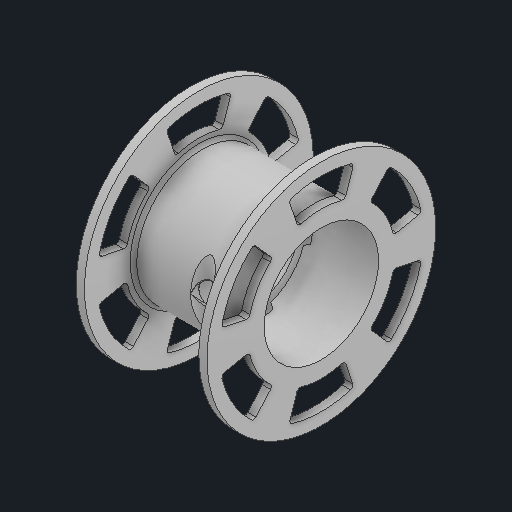
# Autodesk Inventor part: 4_02_Bobine
Saved by Autodesk Inventor 2026 (Build 300175000, 175)
## iProperties
Created: 2025-05-01
Part Number: 4_02_Bobine
Material: Generic
Document SubType Name: Modeling
Designer: AdminForWorker
Density: 1 g/cm^3
Appearance: Default
Title: 4_02_Bobine v3
Author: AdminForWorker
Autodesk Inventor part; units mm, degrees
sketch "Esquisse1" plane through (0, 0, 0) normal (0, 0, 1) x (1, 0, 0)
  line L0 (0.0093, 70) -> (5.0093, 70)
  line L1 (5.0093, 70) -> (5.0093, 40)
  line L2 (0.0093, 70) -> (0.0093, 25.3)
  line L3 (5.0093, 40) -> (75.0093, 40)
  line L4 (75.0093, 40) -> (75.0093, 70)
  line L5 (75.0093, 70) -> (80.0093, 70)
  line L6 (80.0093, 70) -> (80.0093, 35)
  line L7 (80.0093, 35) -> (40.0093, 35)
  line L8 (40.0093, 25.3) -> (40.0093, 35)
  line L9 (-90.7605, 0) -> (228.6248, 0)
  line L10 (40.0093, 25.3) -> (0.0093, 25.3)
  point P0 (0, 0)
  dimension "d2" = 5
  dimension "d3" = 30
  dimension "d4" = 70
  dimension "d5" = 30
  dimension "d6" = 5
  dimension "d7" = 35
  dimension "d8" = 40
  dimension "d9" = 40
  dimension "d10" = 140
  dimension "d12" = 70
  dimension "d20" = 9.7
  constraints: 22 end point, 5 horizontal, 4 perpendicular, 3 vertical
  measures "d2" distance of L0.start L0.end
  measures "d3" distance of L0.end L1.end
  measures "d4" distance of L1.end L3.end
  measures "d5" distance of L3.end L4.end
  measures "d6" distance of L4.end L5.end
  measures "d7" distance of L5.end L6.end
  measures "d8" distance of L6.end L7.end
  measures "d9" distance of L2.end L8.start
  measures "d10" diameter of L0 L9
  measures "d12" diameter of L7 L9
  measures "d20" distance of L8.start L7.end
revolve "Révolution1" add sketch "Esquisse1" angle 360 about axis through (-90.7605, 0, 0) along (1, 0, 0)
sketch "Esquisse2" plane through (0.0093, 0, 0) normal (-1, 0, 0) x (0, 0, 1)
  circle A0 centre (0, 0) radius 30.3 construction
  circle A1 centre (0, 0) radius 35 construction
  line L0 (0, 0) -> (-87.8367, 0) construction
  line L1 (0, 0) -> (94.5103, 0) construction
  line L2 (0, 0) -> (0, 50.6055) construction
  line L3 (0, 0) -> (0, -54.0226) construction
  line L4 (0, 0) -> (-78.2056, 24.1918) construction
  line L5 (0, 0) -> (-24.1308, 78.0083) construction
  line L6 (0, 0) -> (-85.524, -26.4557) construction
  line L7 (0, 0) -> (-24.2483, -78.3883) construction
  line L8 (0, 0) -> (78.2056, 24.1918) construction
  line L9 (0, 0) -> (24.1308, 78.0083) construction
  line L10 (0, 0) -> (85.524, -26.4557) construction
  line L11 (0, 0) -> (24.2483, -78.3883) construction
  line L12 (-28.9467, 8.9543) -> (-33.4368, 10.3432)
  line L13 (-8.9543, 28.9467) -> (-10.3432, 33.4368)
  line L14 (8.9543, 28.9467) -> (10.3432, 33.4368)
  line L15 (28.9467, 8.9543) -> (33.4368, 10.3432)
  line L16 (28.9467, -8.9543) -> (33.4368, -10.3432)
  line L17 (8.9543, -28.9467) -> (10.3432, -33.4368)
  line L18 (-8.9543, -28.9467) -> (-10.3432, -33.4368)
  line L19 (-28.9467, -8.9543) -> (-33.4368, -10.3432)
  arc A2 (33.4368, 10.3432) -> (10.3432, 33.4368) centre (0, 0) ccw
  arc A3 (28.9467, 8.9543) -> (8.9543, 28.9467) centre (0, 0) ccw
  arc A4 (8.9543, -28.9467) -> (28.9467, -8.9543) centre (0, 0) ccw
  arc A5 (10.3432, -33.4368) -> (33.4368, -10.3432) centre (0, 0) ccw
  arc A6 (-28.9467, -8.9543) -> (-8.9543, -28.9467) centre (0, 0) ccw
  arc A7 (-33.4368, -10.3432) -> (-10.3432, -33.4368) centre (0, 0) ccw
  arc A8 (-8.9543, 28.9467) -> (-28.9467, 8.9543) centre (0, 0) ccw
  arc A9 (-10.3432, 33.4368) -> (-33.4368, 10.3432) centre (0, 0) ccw
  dimension "d22" = 60.6
  dimension "d23" = 70
  dimension "d24" = 17.189
  dimension "d25" = 17.189
  dimension "d26" = 17.189
  dimension "d27" = 17.189
  constraints: 40 end point, 16 point on circle, 16 point on line, 9 centre point, 4 concentric, 4 symmetric about line, 2 coincident, 2 horizontal, 2 vertical, 14 other
  measures "d23" diameter of A1
  measures "d24" angle of L4 L0
  measures "d25" angle of L2 L5
  measures "d26" angle of L0 L6
  measures "d27" angle of L3 L7
extrude "Extrusion1" cut sketch "Esquisse2" against normal blind 60
ref_plane "Plan de construction3" through (40.0093, 0, 40) normal (0, 0, 1) x (1, 0, 0)
sketch "Esquisse4" plane through (40.0093, 0, 40) normal (0, 0, 1) x (1, 0, 0)
  line L0 (35, -70) -> (35, 70) projected
  point P0 (-40.0093, 0)
  point P1 (7, 0)
  dimension "d38" = 28
  measures "d38" distance from line of L0 point (7, 0)
hole "Perçage2" at (47.0093, 0, 40) direction (0, 0, -1) diameter 14 end up to surface
sketch "Esquisse5" plane through (0.0093, 0, 0) normal (-1, 0, 0) x (0, 0, 1)
  circle A0 centre (0, 0) radius 40 construction
  circle A1 centre (0, 0) radius 35 projected
  circle A2 centre (0, 0) radius 45 construction
  circle A3 centre (0, 0) radius 62.5 construction
  line L0 (0, 0) -> (93.5731, 0) construction
  line L1 (0, 0) -> (52.3953, -90.7513) construction
  line L2 (0, 0) -> (-52.6354, -91.1672) construction
  line L3 (0, 0) -> (-144.4896, 0) construction
  line L4 (0, 0) -> (-63.0448, 109.1968) construction
  line L5 (0, 0) -> (59.6395, 103.2987) construction
  line L6 (0, 0) -> (-79.7656, 90.2882) construction
  line L7 (0, 0) -> (-41.0094, 122.2745) construction
  line L8 (0, 0) -> (37.125, 110.6925) construction
  line L9 (0, 0) -> (75.0774, 84.9815) construction
  line L10 (0, 0) -> (123.0935, 24.9523) construction
  line L11 (0, 0) -> (-106.2672, 21.5414) construction
  line L12 (0, 0) -> (-63.0448, -109.1968) construction
  line L13 (0, 0) -> (59.6395, -103.2987) construction
  line L14 (0, 0) -> (-79.7656, -90.2882) construction
  line L15 (0, 0) -> (-41.0094, -122.2745) construction
  line L16 (0, 0) -> (37.125, -110.6925) construction
  line L17 (0, 0) -> (75.0774, -84.9815) construction
  line L18 (0, 0) -> (123.0935, -24.9523) construction
  line L19 (0, 0) -> (-106.2672, -21.5414) construction
  line L20 (-14.3091, 42.6644) -> (-19.8738, 59.2561)
  line L21 (14.3091, 42.6644) -> (19.8738, 59.2561)
  line L22 (29.7939, 33.7243) -> (41.3804, 46.8392)
  line L23 (44.103, 8.9401) -> (61.2542, 12.4168)
  line L24 (44.103, -8.9401) -> (61.2542, -12.4168)
  line L25 (29.7939, -33.7243) -> (41.3804, -46.8392)
  line L26 (14.3091, -42.6644) -> (19.8738, -59.2561)
  line L27 (-14.3091, -42.6644) -> (-19.8738, -59.2561)
  line L28 (-29.7939, -33.7243) -> (-41.3804, -46.8392)
  line L29 (-44.103, -8.9401) -> (-61.2542, -12.4168)
  line L30 (-44.103, 8.9401) -> (-61.2542, 12.4168)
  line L31 (-29.7939, 33.7243) -> (-41.3804, 46.8392)
  arc A4 (19.8738, 59.2561) -> (-19.8738, 59.2561) centre (0, 0) ccw
  arc A5 (44.103, 8.9401) -> (29.7939, 33.7243) centre (0, 0) ccw
  arc A6 (14.3091, 42.6644) -> (-14.3091, 42.6644) centre (0, 0) ccw
  arc A7 (61.2542, 12.4168) -> (41.3804, 46.8392) centre (0, 0) ccw
  arc A8 (29.7939, -33.7243) -> (44.103, -8.9401) centre (0, 0) ccw
  arc A9 (41.3804, -46.8392) -> (61.2542, -12.4168) centre (0, 0) ccw
  arc A10 (-14.3091, -42.6644) -> (14.3091, -42.6644) centre (0, 0) ccw
  arc A11 (-19.8738, -59.2561) -> (19.8738, -59.2561) centre (0, 0) ccw
  arc A12 (-44.103, -8.9401) -> (-29.7939, -33.7243) centre (0, 0) ccw
  arc A13 (-61.2542, -12.4168) -> (-41.3804, -46.8392) centre (0, 0) ccw
  arc A14 (-41.3804, 46.8392) -> (-61.2542, 12.4168) centre (0, 0) ccw
  arc A15 (-29.7939, 33.7243) -> (-44.103, 8.9401) centre (0, 0) ccw
  dimension "d47" = 90
  dimension "d48" = 125
  dimension "d46" = 80
  dimension "d50" = 60
  dimension "d51" = 60
  dimension "d52" = 60
  dimension "d53" = 60
  dimension "d54" = 11.459
  dimension "d55" = 11.459
  dimension "d56" = 11.459
  dimension "d57" = 11.459
  dimension "d58" = 11.459
  dimension "d59" = 11.459
  constraints: 64 end point, 24 point on circle, 24 point on line, 13 centre point, 8 symmetric about line, 3 coincident, 2 horizontal, 41 other
  measures "d46" diameter of A0
  measures "d50" angle of L0 L1
  measures "d51" angle of L1 L2
  measures "d52" angle of L5 L0
  measures "d53" angle of L4 L5
  measures "d54" angle of L4 L6
  measures "d55" angle of L7 L4
  measures "d56" angle of L8 L5
  measures "d57" angle of L5 L9
  measures "d58" angle of L10 L0
  measures "d59" angle of L3 L11
extrude "Extrusion2" cut sketch "Esquisse5" against normal through all contours L20 A4 L21 A6 | L22 A7 L23 A5 | L24 A9 L25 A8 | L26 A11 L27 A10 | L28 A13 L29 A12 | L30 A14 L31 A15
ref_plane "Plan de construction4" through (47.0093, 0, 0) normal (-1, 0, 0) x (0, 0, 1)
sketch "Esquisse6" plane through (47.0093, 0, 0) normal (-1, 0, 0) x (0, 0, 1)
  arc A0 (39.9375, 0) -> (41.4418, 19.825) centre (0, 13) ccw
  circle A1 centre (0, 0) radius 25.3 construction
  line L0 (0, 0) -> (92.3783, 0) construction
  arc A2 (41.4418, -19.825) -> (39.9375, 0) centre (0, -13) ccw
  arc A3 (34.9994, -36.2172) -> (41.4418, -19.825) centre (0, -13) ccw
  arc A4 (41.4418, 19.825) -> (34.9994, 36.2172) centre (0, 13) ccw
  dimension "d73" = 42
  constraints: 9 point on circle, 4 centre point, 4 symmetric about line, 2 end point, 1 horizontal, 3 other
  measures "d73" radius of A3
ref_plane "Plan de construction6" through (47.0093, -36.2172, 34.9994) normal (0, 0.8333199, 0.552791) x (-1, 0, 0)
sketch "Esquisse8" plane through (47.0093, -36.2172, 34.9994) normal (0, 0.8333199, 0.552791) x (-1, 0, 0)
  circle A0 centre (0, 0) radius 7
  point P0 (47.0093, -49.1863)
  dimension "d71" = 14
  constraints: 1 centre point
  measures "d71" diameter of A0
sweep "Balayage1" cut profiles "Esquisse8" path "Esquisse6" path curves A3 A2 A0 A4
fillet "Congé5" radius 2 50 edges at (5.0093, -40, 0) (75.0093, -40, 0) (77.5093, 42.6644, 14.3091) (77.5093, 42.6644, -14.3091) (77.5093, 59.2561, -19.8738) (77.5093, 59.2561, 19.8738) (77.5093, 33.7243, -29.7939) (77.5093, 46.8392, -41.3804) (77.5093, 46.8392, 41.3804) (77.5093, 8.9401, -44.103) (77.5093, 12.4168, -61.2542) (77.5093, -8.9401, -44.103) (77.5093, -42.6644, -14.3091) (77.5093, -42.6644, 14.3091) (77.5093, -12.4168, -61.2542) (77.5093, -46.8392, -41.3804) (77.5093, -59.2561, -19.8738) (77.5093, -33.7243, -29.7939) (77.5093, -59.2561, 19.8738) (77.5093, -33.7243, 29.7939) (77.5093, -46.8392, 41.3804) (77.5093, 8.9401, 44.103) (77.5093, -12.4168, 61.2542) (77.5093, -8.9401, 44.103) (77.5093, 12.4168, 61.2542) (77.5093, 33.7243, 29.7939) (2.5093, 8.9401, -44.103) (2.5093, 33.7243, -29.7939) (2.5093, -33.7243, -29.7939) (2.5093, -8.9401, -44.103) (2.5093, -42.6644, 14.3091) (2.5093, -42.6644, -14.3091) (2.5093, -33.7243, 29.7939) (2.5093, -8.9401, 44.103) (2.5093, 33.7243, 29.7939) (2.5093, 8.9401, 44.103) (2.5093, 42.6644, 14.3091) (2.5093, 42.6644, -14.3091) (2.5093, 46.8392, 41.3804) (2.5093, 59.2561, -19.8738) (2.5093, 12.4168, -61.2542) (2.5093, -46.8392, -41.3804) (2.5093, -59.2561, 19.8738) (2.5093, -12.4168, 61.2542) (2.5093, 12.4168, 61.2542) (2.5093, -46.8392, 41.3804) (2.5093, -59.2561, -19.8738) (2.5093, -12.4168, -61.2542) (2.5093, 46.8392, -41.3804) (2.5093, 59.2561, 19.8738)
fillet "Congé6" radius 1 3 edges at (47.0092, 7, 34.4819) (52.3544, -4.52, 36.5081) (41.6642, -4.52, 36.5081)
body "Solid1"
